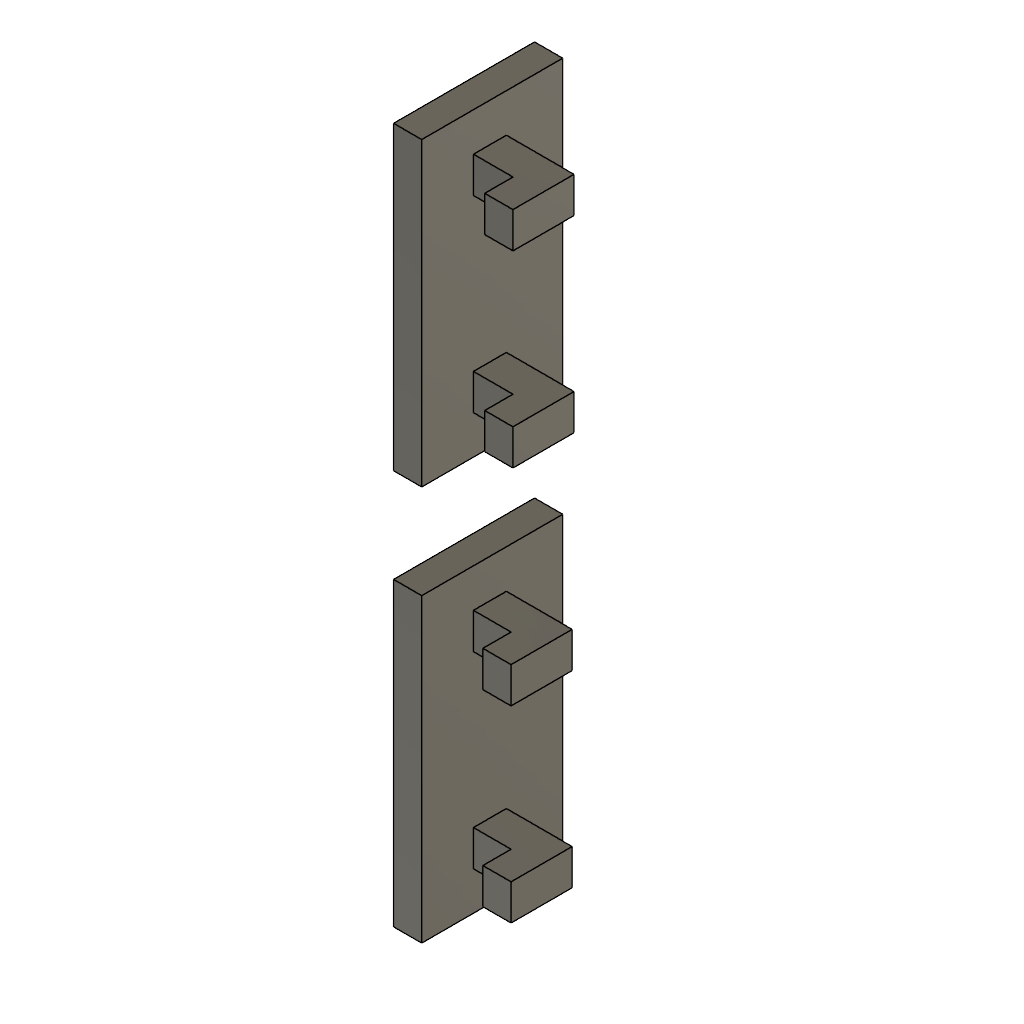
HookDepth_4.0_4.2_v03 (Autodesk Fusion 360 design; units mm, degrees)
part number: 2026-10-19-07-21-53-205
part number: 2026-10-19-07-21-53-526
part number: 2026-10-19-07-21-56-381
Autodesk Fusion 360 part; units mm, degrees
ref_plane "工作平面1" through (0, 0, -16) normal (0, 0, 1) x (1, 0, 0) in component "DEPTH 4.0 mm - FIT ONLY"
sketch "草图1" plane through (0, 0, -16) normal (0, 0, 1) x (1, 0, 0) in component "DEPTH 4.0 mm - FIT ONLY"
  line L0 (-3, 7) -> (0, 7)
  line L1 (0, 7) -> (0, 22)
  line L2 (0, 22) -> (-3, 22)
  line L3 (-3, 22) -> (-3, 7)
extrude "Compact plate 32 x 15 x 3" add sketch "草图1" along normal blind 32 makes body 1 in component "DEPTH 4.0 mm - FIT ONLY"
ref_plane "工作平面2" through (0, 0, -11.9) normal (0, 0, 1) x (1, 0, 0) in component "DEPTH 4.0 mm - FIT ONLY"
sketch "草图2" plane through (0, 0, -11.9) normal (0, 0, 1) x (1, 0, 0) in component "DEPTH 4.0 mm - FIT ONLY"
  line L0 (0, 12.5) -> (4, 12.5)
  line L1 (4, 12.5) -> (4, 9.5)
  line L2 (4, 9.5) -> (7, 9.5)
  line L3 (7, 9.5) -> (7, 16)
  line L4 (7, 16) -> (0, 16)
  line L5 (0, 16) -> (0, 12.5)
extrude "Upper hook 4.0" add sketch "草图2" along normal blind 3.8 bodies 1 in component "DEPTH 4.0 mm - FIT ONLY"
ref_plane "工作平面3" through (0, 0, 8.1) normal (0, 0, 1) x (1, 0, 0) in component "DEPTH 4.0 mm - FIT ONLY"
sketch "草图3" plane through (0, 0, 8.1) normal (0, 0, 1) x (1, 0, 0) in component "DEPTH 4.0 mm - FIT ONLY"
  line L0 (0, 12.5) -> (4, 12.5)
  line L1 (4, 12.5) -> (4, 9.5)
  line L2 (4, 9.5) -> (7, 9.5)
  line L3 (7, 9.5) -> (7, 16)
  line L4 (7, 16) -> (0, 16)
  line L5 (0, 16) -> (0, 12.5)
extrude "Upper hook 4.0 (1)" add sketch "草图3" along normal blind 3.8 bodies 1 in component "DEPTH 4.0 mm - FIT ONLY"
ref_plane "工作平面4" through (0, 0, -8) normal (0, 0, 1) x (1, 0, 0) in component "DEPTH 4.0 mm - FIT ONLY"
sketch "草图4" plane through (0, 0, -8) normal (0, 0, 1) x (1, 0, 0) in component "DEPTH 4.0 mm - FIT ONLY"
  line L0 (-3, 13) -> (-2.4, 13)
  line L1 (-2.4, 13) -> (-2.4, 16.2)
  line L2 (-2.4, 16.2) -> (-3, 16.2)
  line L3 (-3, 16.2) -> (-3, 13)
extrude "Engrave 4.0" cut sketch "草图4" along normal blind 0.8 bodies 1 in component "DEPTH 4.0 mm - FIT ONLY"
ref_plane "工作平面5" through (0, 0, -8) normal (0, 0, 1) x (1, 0, 0) in component "DEPTH 4.0 mm - FIT ONLY"
sketch "草图5" plane through (0, 0, -8) normal (0, 0, 1) x (1, 0, 0) in component "DEPTH 4.0 mm - FIT ONLY"
  line L0 (-3, 12.6) -> (-2.4, 12.6)
  line L1 (-2.4, 12.6) -> (-2.4, 13.4)
  line L2 (-2.4, 13.4) -> (-3, 13.4)
  line L3 (-3, 13.4) -> (-3, 12.6)
extrude "Engrave 4.0 (1)" cut sketch "草图5" along normal blind 4.4 bodies 1 in component "DEPTH 4.0 mm - FIT ONLY"
ref_plane "工作平面6" through (0, 0, -4.4) normal (0, 0, 1) x (1, 0, 0) in component "DEPTH 4.0 mm - FIT ONLY"
sketch "草图6" plane through (0, 0, -4.4) normal (0, 0, 1) x (1, 0, 0) in component "DEPTH 4.0 mm - FIT ONLY"
  line L0 (-3, 13) -> (-2.4, 13)
  line L1 (-2.4, 13) -> (-2.4, 16.2)
  line L2 (-2.4, 16.2) -> (-3, 16.2)
  line L3 (-3, 16.2) -> (-3, 13)
extrude "Engrave 4.0 (2)" cut sketch "草图6" along normal blind 0.8 bodies 1 in component "DEPTH 4.0 mm - FIT ONLY"
ref_plane "工作平面7" through (0, 0, -4.4) normal (0, 0, 1) x (1, 0, 0) in component "DEPTH 4.0 mm - FIT ONLY"
sketch "草图7" plane through (0, 0, -4.4) normal (0, 0, 1) x (1, 0, 0) in component "DEPTH 4.0 mm - FIT ONLY"
  line L0 (-3, 9.8) -> (-2.4, 9.8)
  line L1 (-2.4, 9.8) -> (-2.4, 13)
  line L2 (-2.4, 13) -> (-3, 13)
  line L3 (-3, 13) -> (-3, 9.8)
extrude "Engrave 4.0 (3)" cut sketch "草图7" along normal blind 0.8 bodies 1 in component "DEPTH 4.0 mm - FIT ONLY"
ref_plane "工作平面8" through (0, 0, -1.8) normal (0, 0, 1) x (1, 0, 0) in component "DEPTH 4.0 mm - FIT ONLY"
sketch "草图8" plane through (0, 0, -1.8) normal (0, 0, 1) x (1, 0, 0) in component "DEPTH 4.0 mm - FIT ONLY"
  line L0 (-3, 9) -> (-2.4, 9)
  line L1 (-2.4, 9) -> (-2.4, 10)
  line L2 (-2.4, 10) -> (-3, 10)
  line L3 (-3, 10) -> (-3, 9)
extrude "Engrave 4.0 (4)" cut sketch "草图8" along normal blind 1 bodies 1 in component "DEPTH 4.0 mm - FIT ONLY"
ref_plane "工作平面9" through (0, 0, 1) normal (0, 0, 1) x (1, 0, 0) in component "DEPTH 4.0 mm - FIT ONLY"
sketch "草图9" plane through (0, 0, 1) normal (0, 0, 1) x (1, 0, 0) in component "DEPTH 4.0 mm - FIT ONLY"
  line L0 (-3, 16.2) -> (-2.4, 16.2)
  line L1 (-2.4, 16.2) -> (-2.4, 17)
  line L2 (-2.4, 17) -> (-3, 17)
  line L3 (-3, 17) -> (-3, 16.2)
extrude "Engrave 4.0 (5)" cut sketch "草图9" along normal blind 4.4 bodies 1 in component "DEPTH 4.0 mm - FIT ONLY"
ref_plane "工作平面10" through (0, 0, 4.6) normal (0, 0, 1) x (1, 0, 0) in component "DEPTH 4.0 mm - FIT ONLY"
sketch "草图10" plane through (0, 0, 4.6) normal (0, 0, 1) x (1, 0, 0) in component "DEPTH 4.0 mm - FIT ONLY"
  line L0 (-3, 13) -> (-2.4, 13)
  line L1 (-2.4, 13) -> (-2.4, 16.2)
  line L2 (-2.4, 16.2) -> (-3, 16.2)
  line L3 (-3, 16.2) -> (-3, 13)
extrude "Engrave 4.0 (6)" cut sketch "草图10" along normal blind 0.8 bodies 1 in component "DEPTH 4.0 mm - FIT ONLY"
ref_plane "工作平面11" through (0, 0, 4.6) normal (0, 0, 1) x (1, 0, 0) in component "DEPTH 4.0 mm - FIT ONLY"
sketch "草图11" plane through (0, 0, 4.6) normal (0, 0, 1) x (1, 0, 0) in component "DEPTH 4.0 mm - FIT ONLY"
  line L0 (-3, 9.8) -> (-2.4, 9.8)
  line L1 (-2.4, 9.8) -> (-2.4, 13)
  line L2 (-2.4, 13) -> (-3, 13)
  line L3 (-3, 13) -> (-3, 9.8)
extrude "Engrave 4.0 (7)" cut sketch "草图11" along normal blind 0.8 bodies 1 in component "DEPTH 4.0 mm - FIT ONLY"
ref_plane "工作平面12" through (0, 0, 1) normal (0, 0, 1) x (1, 0, 0) in component "DEPTH 4.0 mm - FIT ONLY"
sketch "草图12" plane through (0, 0, 1) normal (0, 0, 1) x (1, 0, 0) in component "DEPTH 4.0 mm - FIT ONLY"
  line L0 (-3, 9) -> (-2.4, 9)
  line L1 (-2.4, 9) -> (-2.4, 9.8)
  line L2 (-2.4, 9.8) -> (-3, 9.8)
  line L3 (-3, 9.8) -> (-3, 9)
extrude "Engrave 4.0 (8)" cut sketch "草图12" along normal blind 4.4 bodies 1 in component "DEPTH 4.0 mm - FIT ONLY"
ref_plane "工作平面13" through (0, 0, 1) normal (0, 0, 1) x (1, 0, 0) in component "DEPTH 4.0 mm - FIT ONLY"
sketch "草图13" plane through (0, 0, 1) normal (0, 0, 1) x (1, 0, 0) in component "DEPTH 4.0 mm - FIT ONLY"
  line L0 (-3, 9.8) -> (-2.4, 9.8)
  line L1 (-2.4, 9.8) -> (-2.4, 13)
  line L2 (-2.4, 13) -> (-3, 13)
  line L3 (-3, 13) -> (-3, 9.8)
extrude "Engrave 4.0 (9)" cut sketch "草图13" along normal blind 0.8 bodies 1 in component "DEPTH 4.0 mm - FIT ONLY"
ref_plane "工作平面14" through (0, 0, 1) normal (0, 0, 1) x (1, 0, 0) in component "DEPTH 4.0 mm - FIT ONLY"
sketch "草图14" plane through (0, 0, 1) normal (0, 0, 1) x (1, 0, 0) in component "DEPTH 4.0 mm - FIT ONLY"
  line L0 (-3, 13) -> (-2.4, 13)
  line L1 (-2.4, 13) -> (-2.4, 16.2)
  line L2 (-2.4, 16.2) -> (-3, 16.2)
  line L3 (-3, 16.2) -> (-3, 13)
extrude "Engrave 4.0 (10)" cut sketch "草图14" along normal blind 0.8 bodies 1 in component "DEPTH 4.0 mm - FIT ONLY"
ref_plane "工作平面1" through (0, 0, 26) normal (0, 0, 1) x (1, 0, 0) in component "DEPTH 4.2 mm - FIT ONLY"
sketch "草图1 (2)" plane through (0, 0, 26) normal (0, 0, 1) x (1, 0, 0) in component "DEPTH 4.2 mm - FIT ONLY"
  line L0 (-3, 7) -> (0, 7)
  line L1 (0, 7) -> (0, 22)
  line L2 (0, 22) -> (-3, 22)
  line L3 (-3, 22) -> (-3, 7)
extrude "Compact plate 32 x 15 x 3'" add sketch "草图1 (2)" along normal blind 32 separate body makes body 2 in component "DEPTH 4.2 mm - FIT ONLY"
ref_plane "工作平面2" through (0, 0, 30.1) normal (0, 0, 1) x (1, 0, 0) in component "DEPTH 4.2 mm - FIT ONLY"
sketch "草图2 (2)" plane through (0, 0, 30.1) normal (0, 0, 1) x (1, 0, 0) in component "DEPTH 4.2 mm - FIT ONLY"
  line L0 (0, 12.5) -> (4.2, 12.5)
  line L1 (4.2, 12.5) -> (4.2, 9.5)
  line L2 (4.2, 9.5) -> (7.2, 9.5)
  line L3 (7.2, 9.5) -> (7.2, 16)
  line L4 (7.2, 16) -> (0, 16)
  line L5 (0, 16) -> (0, 12.5)
extrude "Upper hook 4.2" add sketch "草图2 (2)" along normal blind 3.8 bodies 2 in component "DEPTH 4.2 mm - FIT ONLY"
ref_plane "工作平面3" through (0, 0, 50.1) normal (0, 0, 1) x (1, 0, 0) in component "DEPTH 4.2 mm - FIT ONLY"
sketch "草图3 (2)" plane through (0, 0, 50.1) normal (0, 0, 1) x (1, 0, 0) in component "DEPTH 4.2 mm - FIT ONLY"
  line L0 (0, 12.5) -> (4.2, 12.5)
  line L1 (4.2, 12.5) -> (4.2, 9.5)
  line L2 (4.2, 9.5) -> (7.2, 9.5)
  line L3 (7.2, 9.5) -> (7.2, 16)
  line L4 (7.2, 16) -> (0, 16)
  line L5 (0, 16) -> (0, 12.5)
extrude "Upper hook 4.2 (1)" add sketch "草图3 (2)" along normal blind 3.8 bodies 2 in component "DEPTH 4.2 mm - FIT ONLY"
ref_plane "工作平面4" through (0, 0, 34) normal (0, 0, 1) x (1, 0, 0) in component "DEPTH 4.2 mm - FIT ONLY"
sketch "草图4 (2)" plane through (0, 0, 34) normal (0, 0, 1) x (1, 0, 0) in component "DEPTH 4.2 mm - FIT ONLY"
  line L0 (-3, 13) -> (-2.4, 13)
  line L1 (-2.4, 13) -> (-2.4, 16.2)
  line L2 (-2.4, 16.2) -> (-3, 16.2)
  line L3 (-3, 16.2) -> (-3, 13)
extrude "Engrave 4.2" cut sketch "草图4 (2)" along normal blind 0.8 bodies 2 in component "DEPTH 4.2 mm - FIT ONLY"
ref_plane "工作平面5" through (0, 0, 34) normal (0, 0, 1) x (1, 0, 0) in component "DEPTH 4.2 mm - FIT ONLY"
sketch "草图5 (2)" plane through (0, 0, 34) normal (0, 0, 1) x (1, 0, 0) in component "DEPTH 4.2 mm - FIT ONLY"
  line L0 (-3, 12.6) -> (-2.4, 12.6)
  line L1 (-2.4, 12.6) -> (-2.4, 13.4)
  line L2 (-2.4, 13.4) -> (-3, 13.4)
  line L3 (-3, 13.4) -> (-3, 12.6)
extrude "Engrave 4.2 (1)" cut sketch "草图5 (2)" along normal blind 4.4 bodies 2 in component "DEPTH 4.2 mm - FIT ONLY"
ref_plane "工作平面6" through (0, 0, 37.6) normal (0, 0, 1) x (1, 0, 0) in component "DEPTH 4.2 mm - FIT ONLY"
sketch "草图6 (2)" plane through (0, 0, 37.6) normal (0, 0, 1) x (1, 0, 0) in component "DEPTH 4.2 mm - FIT ONLY"
  line L0 (-3, 13) -> (-2.4, 13)
  line L1 (-2.4, 13) -> (-2.4, 16.2)
  line L2 (-2.4, 16.2) -> (-3, 16.2)
  line L3 (-3, 16.2) -> (-3, 13)
extrude "Engrave 4.2 (2)" cut sketch "草图6 (2)" along normal blind 0.8 bodies 2 in component "DEPTH 4.2 mm - FIT ONLY"
ref_plane "工作平面7" through (0, 0, 37.6) normal (0, 0, 1) x (1, 0, 0) in component "DEPTH 4.2 mm - FIT ONLY"
sketch "草图7 (2)" plane through (0, 0, 37.6) normal (0, 0, 1) x (1, 0, 0) in component "DEPTH 4.2 mm - FIT ONLY"
  line L0 (-3, 9.8) -> (-2.4, 9.8)
  line L1 (-2.4, 9.8) -> (-2.4, 13)
  line L2 (-2.4, 13) -> (-3, 13)
  line L3 (-3, 13) -> (-3, 9.8)
extrude "Engrave 4.2 (3)" cut sketch "草图7 (2)" along normal blind 0.8 bodies 2 in component "DEPTH 4.2 mm - FIT ONLY"
ref_plane "工作平面8" through (0, 0, 40.2) normal (0, 0, 1) x (1, 0, 0) in component "DEPTH 4.2 mm - FIT ONLY"
sketch "草图8 (2)" plane through (0, 0, 40.2) normal (0, 0, 1) x (1, 0, 0) in component "DEPTH 4.2 mm - FIT ONLY"
  line L0 (-3, 9) -> (-2.4, 9)
  line L1 (-2.4, 9) -> (-2.4, 10)
  line L2 (-2.4, 10) -> (-3, 10)
  line L3 (-3, 10) -> (-3, 9)
extrude "Engrave 4.2 (4)" cut sketch "草图8 (2)" along normal blind 1 bodies 2 in component "DEPTH 4.2 mm - FIT ONLY"
ref_plane "工作平面9" through (0, 0, 43) normal (0, 0, 1) x (1, 0, 0) in component "DEPTH 4.2 mm - FIT ONLY"
sketch "草图9 (2)" plane through (0, 0, 43) normal (0, 0, 1) x (1, 0, 0) in component "DEPTH 4.2 mm - FIT ONLY"
  line L0 (-3, 16.2) -> (-2.4, 16.2)
  line L1 (-2.4, 16.2) -> (-2.4, 17)
  line L2 (-2.4, 17) -> (-3, 17)
  line L3 (-3, 17) -> (-3, 16.2)
extrude "Engrave 4.2 (5)" cut sketch "草图9 (2)" along normal blind 4.4 bodies 2 in component "DEPTH 4.2 mm - FIT ONLY"
ref_plane "工作平面10" through (0, 0, 46.6) normal (0, 0, 1) x (1, 0, 0) in component "DEPTH 4.2 mm - FIT ONLY"
sketch "草图10 (2)" plane through (0, 0, 46.6) normal (0, 0, 1) x (1, 0, 0) in component "DEPTH 4.2 mm - FIT ONLY"
  line L0 (-3, 13) -> (-2.4, 13)
  line L1 (-2.4, 13) -> (-2.4, 16.2)
  line L2 (-2.4, 16.2) -> (-3, 16.2)
  line L3 (-3, 16.2) -> (-3, 13)
extrude "Engrave 4.2 (6)" cut sketch "草图10 (2)" along normal blind 0.8 bodies 2 in component "DEPTH 4.2 mm - FIT ONLY"
ref_plane "工作平面11" through (0, 0, 43) normal (0, 0, 1) x (1, 0, 0) in component "DEPTH 4.2 mm - FIT ONLY"
sketch "草图11 (2)" plane through (0, 0, 43) normal (0, 0, 1) x (1, 0, 0) in component "DEPTH 4.2 mm - FIT ONLY"
  line L0 (-3, 12.6) -> (-2.4, 12.6)
  line L1 (-2.4, 12.6) -> (-2.4, 13.4)
  line L2 (-2.4, 13.4) -> (-3, 13.4)
  line L3 (-3, 13.4) -> (-3, 12.6)
extrude "Engrave 4.2 (7)" cut sketch "草图11 (2)" along normal blind 4.4 bodies 2 in component "DEPTH 4.2 mm - FIT ONLY"
ref_plane "工作平面12" through (0, 0, 43) normal (0, 0, 1) x (1, 0, 0) in component "DEPTH 4.2 mm - FIT ONLY"
sketch "草图12 (2)" plane through (0, 0, 43) normal (0, 0, 1) x (1, 0, 0) in component "DEPTH 4.2 mm - FIT ONLY"
  line L0 (-3, 9.8) -> (-2.4, 9.8)
  line L1 (-2.4, 9.8) -> (-2.4, 13)
  line L2 (-2.4, 13) -> (-3, 13)
  line L3 (-3, 13) -> (-3, 9.8)
extrude "Engrave 4.2 (8)" cut sketch "草图12 (2)" along normal blind 0.8 bodies 2 in component "DEPTH 4.2 mm - FIT ONLY"
ref_plane "工作平面13" through (0, 0, 43) normal (0, 0, 1) x (1, 0, 0) in component "DEPTH 4.2 mm - FIT ONLY"
sketch "草图13 (2)" plane through (0, 0, 43) normal (0, 0, 1) x (1, 0, 0) in component "DEPTH 4.2 mm - FIT ONLY"
  line L0 (-3, 9) -> (-2.4, 9)
  line L1 (-2.4, 9) -> (-2.4, 9.8)
  line L2 (-2.4, 9.8) -> (-3, 9.8)
  line L3 (-3, 9.8) -> (-3, 9)
extrude "Engrave 4.2 (9)" cut sketch "草图13 (2)" along normal blind 4.4 bodies 2 in component "DEPTH 4.2 mm - FIT ONLY"
component "DEPTH 4.0 mm - FIT ONLY" placed x (1, 0, 0) y (0, 1, 0) z (0, 0, 1) at (0, 0, 0)
component "DEPTH 4.2 mm - FIT ONLY" placed x (1, 0, 0) y (0, 1, 0) z (0, 0, 1) at (0, 0, 0)
named bodies: "DEPTH 4.0 mm ENGRAVED - NO LOAD", "DEPTH 4.2 mm ENGRAVED - NO LOAD"
